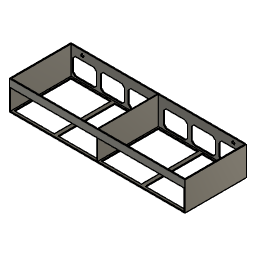
Medium_Holder_PRINT (Autodesk Fusion 360 design; units mm, degrees)
Autodesk Fusion 360 part; units mm, degrees
note: some values were not read from the file. Set by a fixed rule: which face or edge a step refers to.
sketch "Bottom" plane through (0, 0, 0) normal (0, 0, 1) x (1, 0, 0)
  line L0 (0, 0) -> (232.6, 0)
  line L1 (232.6, 0) -> (232.6, 81.6)
  line L2 (232.6, 81.6) -> (0, 81.6)
  line L3 (0, 81.6) -> (0, 0)
  line L4 (1.2, 80.4) -> (231.4, 80.4)
  line L5 (231.4, 80.4) -> (231.4, 1.2)
  line L6 (231.4, 1.2) -> (1.2, 1.2)
  line L7 (1.2, 1.2) -> (1.2, 80.4)
  line L8 (3.2, 3.2) -> (3.2, 78.4)
  line L9 (33.4, 80.4) -> (34.2, 80.4)
  line L10 (34.2, 1.2) -> (33.4, 1.2)
  line L11 (66.4, 80.4) -> (67.2, 80.4)
  line L12 (67.2, 1.2) -> (66.4, 1.2)
  line L13 (99.4, 80.4) -> (100.2, 80.4)
  line L14 (100.2, 1.2032) -> (99.4, 1.2032)
  line L15 (132.4, 80.4) -> (133.2, 80.4)
  line L16 (133.2, 1.2) -> (132.4, 1.2)
  line L17 (165.4, 80.4) -> (166.2, 80.4)
  line L18 (166.2, 1.2) -> (165.4, 1.2)
  line L19 (198.4, 80.4) -> (199.2, 80.4)
  line L20 (199.2, 1.2) -> (198.4, 1.2)
  line L21 (229.4, 78.4) -> (229.4, 3.2)
  line L22 (231.4, 80.4) -> (232.2, 80.4)
  line L23 (232.2, 1.2) -> (231.4, 1.2)
  line L24 (115.9, 78.4) -> (115.9, 3.2)
  line L25 (116.7, 78.4) -> (116.7, 3.2)
  line L26 (116.7, 78.4) -> (116.7, 80.4)
  line L27 (115.9, 78.4) -> (115.9, 80.4)
  line L28 (116.7, 3.2) -> (116.7, 1.2)
  line L29 (115.9, 3.2) -> (115.9, 1.2)
  line L30 (113.9, 78.4) -> (113.9, 3.2)
  line L31 (3.2, 78.4) -> (113.9, 78.4)
  line L32 (113.9, 3.2) -> (3.2, 3.2)
  line L33 (229.4, 78.4) -> (118.7, 78.4)
  line L34 (118.7, 78.4) -> (118.7, 3.2)
  line L35 (229.4, 3.2) -> (118.7, 3.2)
  line L36 (56.2, 78.4) -> (56.2, 3.2)
  line L37 (61.2, 78.4) -> (61.2, 3.2)
  line L38 (171.7, 78.4) -> (171.7, 3.2)
  line L39 (176.7, 3.2) -> (176.7, 78.4)
  dimension "d1" = 1.2
  dimension "d2" = 1.2
  dimension "d3" = 1.2
  dimension "d4" = 1.2
  dimension "d5" = 2
  dimension "d8" = 81.6
  dimension "d52" = 2
  dimension "d173" = 112.7
  dimension "d174" = 112.7
  dimension "d175" = 0.8
  dimension "d190" = 2
  dimension "d191" = 2
  dimension "d192" = 2
  dimension "d193" = 2
  dimension "d194" = 2
  dimension "d195" = 2
  dimension "d203" = 5
  dimension "d204" = 53
  dimension "d206" = 5
  dimension "d207" = 53
  constraint horizontal L0
  constraint vertical L1
  constraint horizontal L2
  constraint vertical L3
  constraint coincident L0.start L3.end
  constraint horizontal L4
  constraint vertical L5
  constraint horizontal L6
  constraint vertical L7
  constraint vertical L8
  constraint horizontal L9
  constraint coincident L6 L10.start
  constraint coincident L4 L9.start
  constraint horizontal L11
  constraint horizontal L12
  constraint coincident L4 L11.start
  constraint horizontal L13
  constraint horizontal L14
  constraint coincident L4 L13.start
  constraint horizontal L15
  constraint horizontal L16
  constraint coincident L4 L15.start
  constraint horizontal L17
  constraint horizontal L18
  constraint coincident L4 L17.start
  constraint horizontal L19
  constraint horizontal L20
  constraint coincident L4 L19.start
  constraint vertical L21
  constraint horizontal L22
  constraint horizontal L23
  constraint coincident L4 L5.start
  constraint coincident L4 L26.end
  constraint perpendicular L4 L26
  constraint coincident L4 L27.end
  constraint perpendicular L4 L27
  constraint coincident L6 L28.end
  constraint perpendicular L6 L28
  constraint coincident L6 L29.end
  constraint perpendicular L6 L29
  constraint perpendicular L30 L31
  constraint perpendicular L8 L32
  constraint perpendicular L24 L33
  constraint perpendicular L34 L35
  constraint coincident L31 L36.start
  constraint coincident L32 L36.end
  constraint perpendicular L32 L36
  constraint coincident L31 L37.start
  constraint coincident L32 L37.end
  constraint perpendicular L32 L37
  constraint coincident L33 L38.start
  constraint coincident L35 L38.end
  constraint perpendicular L35 L38
  constraint coincident L35 L39.start
  constraint coincident L33 L39.end
  constraint perpendicular L33 L39
  measures "d1" distance of L3 L7
  measures "d2" distance of L2 L4
  measures "d3" distance of L0 L6
  measures "d4" distance of L1 L5
  measures "d5" distance of L7 L8
  measures "d8" distance of L0.start L2.end
  measures "d52" distance of L5 L21
  measures "d173" distance of L8 L24
  measures "d174" distance of L21 L25
  measures "d175" distance of L24 L25
  measures "d190" distance of L24 L30
  measures "d191" distance of L4 L31
  measures "d192" distance of L6 L32
  measures "d193" distance of L25 L34
  measures "d194" distance of L6 L35
  measures "d195" distance of L4 L33
  measures "d203" distance of L36 L37
  measures "d204" distance of L8 L36
  measures "d206" distance of L38 L39
  measures "d207" distance of L34 L38
extrude "Extrude2" add sketch "Bottom" along normal blind 38.2 contours L0 L1 L2 L3 | L4 L6 L24 L25 L26 L27 L28 L29
sketch "Front" plane through (0, 0, 0) normal (0, -1, 0) x (1, 0, 0)
  line L0 (0, 0) -> (232.6, 0)
  line L1 (232.6, 0) -> (232.6, 38.2)
  line L2 (232.6, 38.2) -> (0, 38.2)
  line L3 (0, 38.2) -> (0, 0)
  line L4 (1.2, 28.2) -> (33.4, 28.2)
  line L5 (33.4, 1.2) -> (1.2, 1.2)
  line L6 (1.2, 1.2) -> (1.2, 28.2)
  line L7 (1.2, 0) -> (1.2, 38.2)
  line L8 (231.4, 28.2) -> (231.4, 1.2)
  line L9 (33.4, 28.2) -> (231.4, 28.2)
  line L10 (231.4, 1.2) -> (33.4, 1.2)
  dimension "d80" = 27
  dimension "d83" = 10
  dimension "d91" = 27
  dimension "d294" = 1.2
  constraint horizontal L4
  constraint horizontal L5
  constraint vertical L6
  constraint collinear L6 L7
  constraint vertical L8
  constraint perpendicular L8 L9
  measures "d80" distance of L4.start L5.end
  measures "d83" distance of L2 L4
  measures "d91" distance of L8.start L8.end
  measures "d294" distance of L1 L8
sketch "Back" plane through (0, 80.4, 0) normal (0, -1, 0) x (1, 0, 0)
  line L0 (231.4, 0) -> (231.4, 38.2)
  line L1 (115.9, 38.2) -> (1.2, 38.2)
  line L2 (1.2, 38.2) -> (1.2, 0)
  line L3 (3.2, 23) -> (3.2, 7)
  line L4 (115.9, 0) -> (115.9, 38.2)
  line L5 (116.7, 38.2) -> (116.7, 0)
  line L6 (231.4, 38.2) -> (116.7, 38.2)
  line L7 (116.7, 0) -> (231.4, 0)
  line L8 (1.2, 0) -> (115.9, 0)
  line L9 (3.2, 23) -> (6.7355, 26.5355)
  line L10 (3.2, 23) -> (8.2, 23) construction
  line L11 (6.7355, 26.5355) -> (31.7355, 26.5355)
  line L12 (31.7355, 26.5355) -> (35.2711, 23)
  line L13 (31.7355, 26.5355) -> (36.7355, 26.5355) construction
  line L14 (35.2711, 23) -> (35.2711, 7)
  line L15 (35.2711, 7) -> (31.7355, 3.4645)
  line L16 (3.2, 7) -> (6.7355, 3.4645)
  line L17 (3.2, 7) -> (8.2, 7) construction
  line L18 (6.7355, 3.4645) -> (31.7355, 3.4645)
  line L19 (43.6066, 26.5355) -> (68.6066, 26.5355)
  line L20 (40.0711, 23) -> (43.6066, 26.5355)
  line L21 (40.0711, 23) -> (40.0711, 7)
  line L22 (40.0711, 7) -> (43.6066, 3.4645)
  line L23 (43.6066, 3.4645) -> (68.6066, 3.4645)
  line L24 (72.1421, 7) -> (68.6066, 3.4645)
  line L25 (72.1421, 23) -> (72.1421, 7)
  line L26 (68.6066, 26.5355) -> (72.1421, 23)
  line L27 (80.4777, 26.5355) -> (105.4777, 26.5355)
  line L28 (76.9421, 23) -> (80.4777, 26.5355)
  line L29 (76.9421, 23) -> (76.9421, 7)
  line L30 (76.9421, 7) -> (80.4777, 3.4645)
  line L31 (80.4777, 3.4645) -> (105.4777, 3.4645)
  line L32 (109.0132, 7) -> (105.4777, 3.4645)
  line L33 (109.0132, 23) -> (109.0132, 7)
  line L34 (105.4777, 26.5355) -> (109.0132, 23)
  line L35 (127.1223, 26.5355) -> (152.1223, 26.5355)
  line L36 (123.5868, 23) -> (127.1223, 26.5355)
  line L37 (123.5868, 23) -> (123.5868, 7)
  line L38 (123.5868, 7) -> (127.1223, 3.4645)
  line L39 (127.1223, 3.4645) -> (152.1223, 3.4645)
  line L40 (155.6579, 7) -> (152.1223, 3.4645)
  line L41 (155.6579, 23) -> (155.6579, 7)
  line L42 (152.1223, 26.5355) -> (155.6579, 23)
  line L43 (163.9934, 26.5355) -> (188.9934, 26.5355)
  line L44 (160.4579, 23) -> (163.9934, 26.5355)
  line L45 (160.4579, 23) -> (160.4579, 7)
  line L46 (160.4579, 7) -> (163.9934, 3.4645)
  line L47 (163.9934, 3.4645) -> (188.9934, 3.4645)
  line L48 (192.5289, 7) -> (188.9934, 3.4645)
  line L49 (192.5289, 23) -> (192.5289, 7)
  line L50 (188.9934, 26.5355) -> (192.5289, 23)
  line L51 (200.8645, 26.5355) -> (225.8645, 26.5355)
  line L52 (197.3289, 23) -> (200.8645, 26.5355)
  line L53 (197.3289, 23) -> (197.3289, 7)
  line L54 (197.3289, 7) -> (200.8645, 3.4645)
  line L55 (200.8645, 3.4645) -> (225.8645, 3.4645)
  line L56 (229.4, 7) -> (225.8645, 3.4645)
  line L57 (229.4, 23) -> (229.4, 7)
  line L58 (225.8645, 26.5355) -> (229.4, 23)
  line L59 (232.6, 0) -> (232.6, 38.2)
  dimension "d102" = 2
  dimension "d211" = 16
  dimension "d214" = 7
  dimension "d216" = 5
  dimension "d217" = 45
  dimension "d218" = 25
  dimension "d219" = 45
  dimension "d220" = 5
  dimension "d221" = 135
  dimension "d222" = 5
  dimension "d223" = 45
  dimension "d224" = 5
  dimension "d225" = 16
  dimension "d226" = 5
  dimension "d227" = 25
  dimension "d228" = 5
  dimension "d229" = 135
  dimension "d230" = 5
  dimension "d231" = 5
  dimension "d232" = 16
  dimension "d233" = 5
  dimension "d234" = 25
  dimension "d235" = 5
  dimension "d236" = 135
  dimension "d237" = 5
  dimension "d238" = 5
  dimension "d239" = 16
  dimension "d240" = 5
  dimension "d241" = 25
  dimension "d242" = 5
  dimension "d243" = 135
  dimension "d244" = 5
  dimension "d245" = 5
  dimension "d246" = 16
  dimension "d247" = 5
  dimension "d248" = 25
  dimension "d249" = 5
  dimension "d250" = 135
  dimension "d251" = 5
  dimension "d252" = 5
  dimension "d253" = 16
  dimension "d254" = 5
  dimension "d255" = 25
  dimension "d256" = 5
  dimension "d257" = 135
  dimension "d258" = 5
  dimension "d259" = 5
  dimension "d260" = 4.8
  dimension "d261" = 4.8
  dimension "d262" = 4.8
  dimension "d263" = 4.8
  dimension "d264" = 23.0711
  dimension "d265" = 3.4645
  dimension "d266" = 32.0711
  dimension "d267" = 3.4645
  dimension "d268" = 3.2
  dimension "d269" = 6.8868
  dimension "d270" = 135
  dimension "d272" = 135
  dimension "d273" = 23.0711
  dimension "d274" = 135
  dimension "d275" = 23.0711
  dimension "d279" = 135
  dimension "d280" = 23.0711
  dimension "d281" = 135
  dimension "d283" = 32.0711
  dimension "d284" = 32.0711
  dimension "d285" = 135
  dimension "d286" = 135
  dimension "d287" = 23.0711
  dimension "d288" = 135
  dimension "d290" = 3.4645
  dimension "d292" = 135
  dimension "d297" = 3.4645
  dimension "d298" = 3.4645
  constraint parallel L2 L3
  constraint horizontal L10
  constraint horizontal L11
  constraint horizontal L13
  constraint vertical L14
  constraint horizontal L17
  constraint horizontal L19
  constraint vertical L25
  constraint horizontal L27
  constraint vertical L33
  constraint horizontal L35
  constraint vertical L41
  constraint horizontal L43
  constraint vertical L49
  constraint horizontal L51
  constraint vertical L57
  measures "d102" distance of L2 L3
  measures "d211" distance of L3.end L3.start
  measures "d214" distance of L3.end L8
  measures "d216" distance of L3.start L9.end
  measures "d217" angle of L9 L10
  measures "d218" distance of L9.end L11.end
  measures "d219" angle of L12 L13
  measures "d220" distance of L11.end L12.end
  measures "d221" angle of L14 L15
  measures "d222" distance of L14.end L15.end
  measures "d223" angle of L16 L17
  measures "d224" distance of L3.end L16.end
  measures "d225" distance of L20.start L21.end
  measures "d226" distance of L19.start L20.start
  measures "d227" distance of L19.start L19.end
  measures "d228" distance of L25.start L19.end
  measures "d229" angle of L24 L25
  measures "d230" distance of L23.end L24.start
  measures "d231" distance of L22.end L21.end
  measures "d232" distance of L28.start L29.end
  measures "d233" distance of L27.start L28.start
  measures "d234" distance of L27.start L27.end
  measures "d235" distance of L33.start L27.end
  measures "d236" angle of L32 L33
  measures "d237" distance of L31.end L32.start
  measures "d238" distance of L30.end L29.end
  measures "d239" distance of L36.start L37.end
  measures "d240" distance of L35.start L36.start
  measures "d241" distance of L35.start L35.end
  measures "d242" distance of L41.start L35.end
  measures "d243" angle of L40 L41
  measures "d244" distance of L39.end L40.start
  measures "d245" distance of L38.end L37.end
  measures "d246" distance of L44.start L45.end
  measures "d247" distance of L43.start L44.start
  measures "d248" distance of L43.start L43.end
  measures "d249" distance of L49.start L43.end
  measures "d250" angle of L48 L49
  measures "d251" distance of L47.end L48.start
  measures "d252" distance of L46.end L45.end
  measures "d253" distance of L52.start L53.end
  measures "d254" distance of L51.start L52.start
  measures "d255" distance of L51.start L51.end
  measures "d256" distance of L57.start L51.end
  measures "d257" angle of L56 L57
  measures "d258" distance of L55.end L56.start
  measures "d259" distance of L54.end L53.end
  measures "d260" distance of L14 L21
  measures "d261" distance of L25 L29
  measures "d262" distance of L49 L53
  measures "d263" distance of L41 L45
  measures "d264" distance of L35 L39
  measures "d265" distance of L7 L39
  measures "d266" distance of L37 L41
  measures "d267" distance of L7 L47
  measures "d268" distance of L57 L59
  measures "d269" distance of L5 L37
  measures "d270" angle of L43 L44
  measures "d272" angle of L43 L50
  measures "d273" distance of L43 L47
  measures "d274" angle of L51 L52
  measures "d275" distance of L51 L55
  measures "d279" angle of L35 L36
  measures "d280" distance of L27 L31
  measures "d281" angle of L27 L34
  measures "d283" distance of L29 L33
  measures "d284" distance of L21 L25
  measures "d285" angle of L19 L20
  measures "d286" angle of L19 L26
  measures "d287" distance of L19 L23
  measures "d288" angle of L20 L21
  measures "d290" distance of L8 L23
  measures "d292" angle of L15 L18
  measures "d297" distance of L8 L31
  measures "d298" distance of L7 L55
sketch "Mounting" plane through (0, 80.4, 0) normal (0, -1, 0) x (1, 0, 0)
  line L0 (231.4, 0) -> (231.4, 38.2)
  line L1 (115.9, 38.2) -> (1.2, 38.2)
  line L2 (1.2, 38.2) -> (1.2, 0)
  circle A0 centre (216.3, 32.2) radius 2
  circle A1 centre (16.3, 32.2) radius 2
  line L3 (115.9, 0) -> (115.9, 38.2)
  line L4 (116.7, 38.2) -> (116.7, 0)
  line L5 (231.4, 38.2) -> (116.7, 38.2)
  line L6 (116.7, 0) -> (231.4, 0)
  line L7 (1.2, 0) -> (115.9, 0)
  dimension "d165" = 4
  dimension "d166" = 4
  dimension "d167" = 15.1
  dimension "d168" = 6
  dimension "d169" = 15.1
  dimension "d170" = 6
  measures "d165" diameter of A0
  measures "d166" diameter of A1
  measures "d167" distance of L2 A1.centre
  measures "d168" distance of L1 A1.centre
  measures "d169" distance of L0 A0.centre
  measures "d170" distance of L1 A0.centre
extrude "Extrude9" cut sketch "Front" against normal up to surface (1.2 mm away) contours L4 L5 L6 L7 L8 L9 L10
extrude "Extrude10" cut sketch "Back" against normal blind 1.2 contours L3 L9 L11 L12 L14 L15 L16 L18 | L19 L20 L21 L22 L23 L24 L25 L26 | L27 L28 L29 L30 L31 L32 L33 L34 | L35 L36 L37 L38 L39 L40 L41 L42 | L43 L44 L45 L46 L47 L48 L49 L50 | L51 L52 L53 L54 L55 L56 L57 L58
extrude "Extrude11" cut sketch "Mounting" against normal blind 1.2 contours A0 | A1
extrude "Extrude12" add sketch "Bottom" along normal up to surface (1.2 mm away) contours L4 L6 L7 L9 L10 L11 L12 L13 L24 L27 L29
extrude "Extrude13" add sketch "Bottom" along normal up to surface (1.2 mm away) contours L4 L5 L6 L15 L16 L17 L18 L19 L20 L25 L26 L28 | L31 L32 L36 L37
extrude "Extrude14" add 1 faces at (116.1667, 1.2, 19.2) along direction (0, -1, 0) up to surface (1.2 mm away)
extrude "Extrude15" add sketch "Bottom" along normal blind 1.2 contours L33 L35 L38 L39
equation "d173 = ( ( 226.2 / 2 ) * 1 mm ) - 0.4 mm"
equation "d174 = ( ( 226.2 / 2 ) * 1 mm ) - 0.4 mm"
